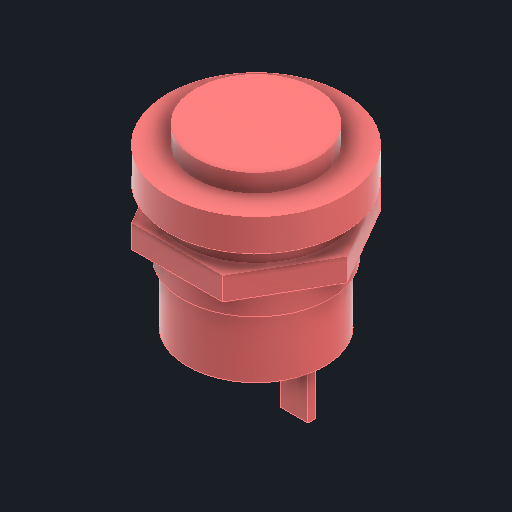
# Autodesk Inventor part: button_16mm_momentary
Saved by Autodesk Inventor 2027.1 (Build 311270010, 270A)
## iProperties
Created: 2026-10-29
Part Number: button_16mm_momentary
Material: Generic
Document SubType Name: Modeling
Designer: alexg
Density: 1 g/cm^3
Appearance: Smooth - Red
Author: alexg
Autodesk Inventor part; units mm, degrees
sketch "Flange sketch" plane through (0, 0, 0) normal (0, 1, 0) x (-1, 0, 0)
  circle A0 centre (0, 0) radius 9.5
  constraints: 1 centre point
extrude "Flange" add sketch "Flange sketch" along normal blind 3.5
ref_plane "Work Plane1" through (0, 3.5, 0) normal (0, 1, 0) x (-1, 0, 0)
sketch "Cap sketch" plane through (0, 3.5, 0) normal (0, 1, 0) x (-1, 0, 0)
  circle A0 centre (0, 0) radius 6.5
  constraints: 1 centre point
extrude "Cap" add sketch "Cap sketch" along normal blind 2
sketch "Thread M16x1 (flat) sketch" plane through (0, 0, 0) normal (0, 1, 0) x (-1, 0, 0)
  arc A0 (3.8471, -6.9) -> (-3.8471, -6.9) centre (0, 0) ccw
  line L0 (-3.8471, -6.9) -> (3.8471, -6.9)
  constraints: 2 end point, 2 point on circle, 1 centre point
extrude "Thread M16x1 (flat)" add sketch "Thread M16x1 (flat) sketch" against normal blind 7
ref_plane "Work Plane2" through (0, -2, 0) normal (0, 1, 0) x (-1, 0, 0)
sketch "Nut sketch" plane through (0, -2, 0) normal (0, 1, 0) x (-1, 0, 0)
  line L0 (-9.815, 0) -> (-4.9075, 8.5)
  line L1 (-4.9075, 8.5) -> (4.9075, 8.5)
  line L2 (4.9075, 8.5) -> (9.815, 0)
  line L3 (9.815, 0) -> (4.9075, -8.5)
  line L4 (4.9075, -8.5) -> (-4.9075, -8.5)
  line L5 (-4.9075, -8.5) -> (-9.815, 0)
  constraints: 12 end point
extrude "Nut" add sketch "Nut sketch" against normal blind 2.5
ref_plane "Work Plane3" through (0, -7, 0) normal (0, 1, 0) x (-1, 0, 0)
sketch "Body sketch" plane through (0, -7, 0) normal (0, 1, 0) x (-1, 0, 0)
  circle A0 centre (0, 0) radius 7.4
  constraints: 1 centre point
extrude "Body" add sketch "Body sketch" against normal blind 6.5
ref_plane "Work Plane4" through (0, -13.5, 0) normal (0, 1, 0) x (-1, 0, 0)
sketch "Solder lugs sketch" plane through (0, -13.5, 0) normal (0, 1, 0) x (-1, 0, 0)
  line L0 (6, -0.4) -> (3, -0.4)
  line L1 (3, -0.4) -> (3, 0.4)
  line L2 (3, 0.4) -> (6, 0.4)
  line L3 (6, 0.4) -> (6, -0.4)
  line L4 (-3, -0.4) -> (-6, -0.4)
  line L5 (-6, -0.4) -> (-6, 0.4)
  line L6 (-6, 0.4) -> (-3, 0.4)
  line L7 (-3, 0.4) -> (-3, -0.4)
  constraints: 16 end point, 4 parallel, 2 horizontal, 2 perpendicular
extrude "Solder lugs" add sketch "Solder lugs sketch" against normal blind 5.8
body "Solid1"
